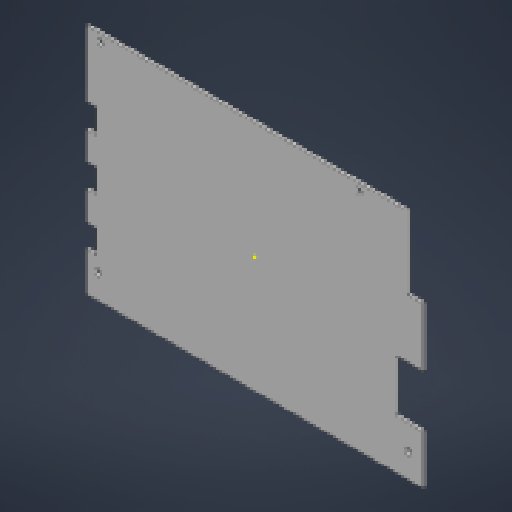
# Autodesk Inventor part: 板子
Saved by Autodesk Inventor 2025 (Build 290162000, 162)
## iProperties
Created: 2025-11-13
Part Number: 板子
Material: 常规
Document SubType Name: Modeling
Designer: HZD
Density: 1 g/cm^3
Appearance: 默认
Author: HZD
Autodesk Inventor part; units mm, degrees
ref_plane "YZ Plane" through (0, 0, 0) normal (1, 0, 0) x (0, 1, 0)
ref_plane "XZ Plane" through (0, 0, 0) normal (0, 1, 0) x (-1, 0, 0)
ref_plane "XY Plane" through (0, 0, 0) normal (0, 0, 1) x (1, 0, 0)
sketch "草图1" plane through (0, 0, 0) normal (0, 0, 1) x (1, 0, 0)
  line L0 (33, -23) -> (-33, -23)
  line L1 (-33, -23) -> (-33, 23)
  line L2 (-33, 23) -> (33, 23)
  line L3 (33, 23) -> (33, -23)
  line L4 (33, -23) -> (-33, 23) construction
  line L5 (-33, -23) -> (33, 23) construction
  line L6 (-32.5, -22.5) -> (32.5, -22.5)
  line L7 (32.5, -22.5) -> (32.5, 22.5)
  line L8 (32.5, 22.5) -> (-32.5, 22.5)
  line L9 (-32.5, 22.5) -> (-32.5, -22.5)
  circle A0 centre (29.5983, -17.8) radius 1.5 projected
  circle A1 centre (-30.4017, -17.8) radius 1.5 projected
  circle A2 centre (-29.9017, 21) radius 1.5 projected
  circle A3 centre (20.0983, 21.0127) radius 0.6 projected
  circle A4 centre (-29.9017, 21) radius 0.6 projected
  circle A5 centre (29.5983, -17.8) radius 0.6 projected
  circle A6 centre (-30.4017, -17.8) radius 1.5 projected
  circle A7 centre (-30.4017, -17.8) radius 0.6 projected
  line L10 (32.5, -12.8922) -> (27.2799, -12.8922)
  line L11 (27.2799, -12.8922) -> (27.2799, -2.8922)
  line L12 (27.2799, -2.8922) -> (32.5, -2.8922)
  line L13 (32.5, -2.8922) -> (32.5, -12.8922)
  line L14 (32.5, 8.5) -> (29.5, 8.5)
  line L15 (29.5, 8.5) -> (29.5, 22.5)
  line L16 (29.5, 22.5) -> (32.5, 22.5)
  line L17 (32.5, 22.5) -> (32.5, 8.5)
  line L18 (-33.1643, -14.95) -> (-33.1643, -10.45) projected
  line L19 (-33.0266, -4.849) -> (-33.0127, -0.349) projected
  line L20 (-32.9958, 5.151) -> (-32.982, 9.651) projected
  line L21 (-32.5, -14.95) -> (-30.6094, -14.95)
  line L22 (-30.6094, -14.95) -> (-30.6094, -10.45)
  line L23 (-30.6094, -10.45) -> (-32.5, -10.45)
  line L24 (-32.5, -10.45) -> (-32.5, -14.95)
  line L25 (-30.6094, -4.849) -> (-32.5, -4.849)
  line L26 (-32.5, -4.849) -> (-32.5, -0.349)
  line L27 (-32.5, -0.349) -> (-30.6094, -0.349)
  line L28 (-30.6094, -0.349) -> (-30.6094, -4.849)
  line L29 (-30.6094, 5.151) -> (-32.5, 5.151)
  line L30 (-32.5, 5.151) -> (-32.5, 9.651)
  line L31 (-32.5, 9.651) -> (-30.6094, 9.651)
  line L32 (-30.6094, 9.651) -> (-30.6094, 5.151)
  line L33 (-33.9958, 5.1541) -> (-32.9958, 5.151)
  line L34 (-33.982, 9.6541) -> (-32.982, 9.651)
  line L35 (-34.0127, -0.3459) -> (-33.0127, -0.349)
  line L36 (-34.0266, -4.8459) -> (-33.0266, -4.849)
  point P0 (0, 0)
  point P1 (-29.9017, 22.5)
  point P2 (-32.5, -0.349)
  dimension "d0" = 66
  dimension "d1" = 46
  dimension "d4" = 0.5
  dimension "d5" = 10
  dimension "d6" = 14
  dimension "d7" = 3
  constraints: 68 end point, 14 parallel, 10 point on line, 7 perpendicular, 6 horizontal, 4 collinear, 2 midpoint, 11 other
  measures "d0" distance of L1.end L2.end
  measures "d1" distance of L2.end L0.start
  measures "d4" distance between parallel lines of L0 L6
  measures "d5" distance between parallel lines of L12 L10
  measures "d6" distance of L14.end L15.end
  measures "d7" distance between parallel lines of L17 L15
extrude "拉伸1" add sketch "草图1" along normal blind 0.5 contours A2 | L9 L21 L22 L23 L25 L28 L27 L29 L32 L31 L8 L15 L14 L7 L12 L11 L10 L6 | A0 | A1
sketch "草图3" plane through (0, 0, 0.5) normal (0, 0, 1) x (1, 0, 0)
  point P0 (0, 0)
